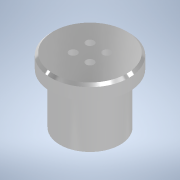
# Autodesk Inventor part: 1.5_3_SpacerA
Saved by Autodesk Inventor 2021 (Build 250183000, 183)
## iProperties
Created: 2025-11-21
Part Number: 1.5_3_SpacerA
Material: Aluminum 6061
Document SubType Name: Modeling
Designer: Admin
Density: 2.7 g/cm^3
Appearance: Aluminum - Flat
Author: Admin
Autodesk Inventor part; units mm, degrees
ref_plane "YZ Plane" through (0, 0, 0) normal (1, 0, 0) x (0, 1, 0)
ref_plane "XZ Plane" through (0, 0, 0) normal (0, 1, 0) x (-1, 0, 0)
ref_plane "XY Plane" through (0, 0, 0) normal (0, 0, 1) x (1, 0, 0)
sketch "Sketch1" plane through (0, 0, 0) normal (0, 1, 0) x (-1, 0, 0)
  circle A0 centre (0, 0) radius 25
  circle A1 centre (0, 0) radius 17.5
  point P0 (-7.8458, 0)
  dimension "d0" = 50
  dimension "d1" = 35
  dimension "d15" = 0
  constraints: 2 centre point, 2 coincident
  measures "d0" diameter of A0
  measures "d1" diameter of A1
  measures "d15" vertical distance of point (-7.846, 0) point (0, 0)
extrude "Extrusion1" add sketch "Sketch1" along normal blind 42
sketch "Sketch3" plane through (0, 42, 0) normal (0, 1, 0) x (1, 0, 0)
  circle A0 centre (0, 0) radius 32.5
  dimension "d26" = 65
  constraints: 1 centre point, 1 coincident
  measures "d26" diameter of A0
extrude "Extrusion3" add sketch "Sketch3" along normal blind 12
fillet "Fillet2" radius 0.5 1 edges at (25, 42, 0)
sketch "Sketch4" plane through (0, 54, 0) normal (0, 1, 0) x (1, 0, 0)
  circle A0 centre (0, 0) radius 17.5 projected
  line L0 (7, -7) -> (-7, -7) construction
  line L1 (-7, -7) -> (-7, 7) construction
  line L2 (-7, 7) -> (7, 7) construction
  line L3 (7, 7) -> (7, -7) construction
  line L4 (7, -7) -> (-7, 7) construction
  line L5 (-7, -7) -> (7, 7) construction
  dimension "d31" = 14
  constraints: 12 end point, 4 coincident, 2 midpoint, 2 parallel, 2 perpendicular, 1 horizontal
  measures "d31" distance of L0.end L1.end
hole "Hole1" at (-7, 54, 7) at (-7, 54, -7) at (7, 54, -7) at (7, 54, 7) direction (0, -1, 0) diameter 6.6 end through all counterbore diameter 11 counterbore depth 3 clearance for "Slotted Cheese Head Screw ISO 1207" size "M6" standard "ISO"
chamfer "Chamfer6" distance 2 angle 45 1 edges at (-32.5, 54, 0)
fillet "Fillet3" radius 1 1 edges at (17.5, 42, 0)
chamfer "Chamfer7" distance 2 angle 45 1 edges at (17.5, 0, 0)
body "Solid1"
